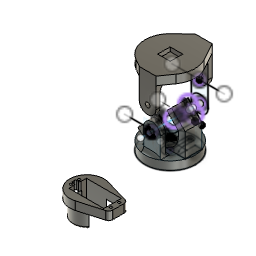
2 Axis Animitronic Neck (Autodesk Fusion 360 design; units mm, degrees)
Autodesk Fusion 360 part; units mm, degrees
sketch "Sketch1" plane through (0, 0, 0) normal (0, 0, 1) x (1, 0, 0)
  circle A0 centre (0, 0) radius 15 construction
  line L0 (0, 5) -> (-39.2157, 5) construction
  line L1 (0, -5) -> (-39.2157, -5) construction
  circle A1 centre (-14.1421, -5) radius 1.5
  circle A2 centre (-14.1421, 5) radius 1.5
  line L2 (-14.1421, -5) -> (-14.1421, 5) construction
  line L3 (33.8579, -5) -> (33.8579, 5) construction
  circle A3 centre (33.8579, 5) radius 1.5
  circle A4 centre (33.8579, -5) radius 1.5
  line L4 (0, -10.5) -> (30.8579, -10.5)
  line L5 (0, 10.5) -> (30.8579, 10.5)
  line L6 (-14.1421, 0) -> (33.8579, 0) construction
  line L7 (30.8579, 0) -> (30.8579, -10.5)
  line L8 (30.8579, 0) -> (30.8579, 10.5)
  line L9 (-11.1421, 0) -> (-11.1421, 10.5)
  line L10 (-11.1421, 0) -> (-11.1421, -10.5)
  line L11 (37.8579, 0) -> (37.8579, 10.5)
  line L12 (37.8579, 0) -> (37.8579, -10.5)
  line L13 (37.8579, 10.5) -> (5.6339, 19.7106)
  line L14 (37.8579, -10.5) -> (5.6339, -19.7106)
  line L15 (0, 10.5) -> (-11.1421, 10.5)
  line L16 (0, -10.5) -> (-11.1421, -10.5)
  arc A5 (5.6339, 19.7106) -> (5.6339, -19.7106) centre (0, 0) ccw
  arc A6 (12.8896, 10.5) -> (12.8896, -10.5) centre (0, 0) ccw
  dimension "d1" = 33.25
  dimension "d3" = 30
  dimension "d6" = 3
  dimension "d7" = 3
  dimension "d8" = 48
  dimension "d9" = 3
  dimension "d10" = 3
  constraint coincident A0.centre A5.centre
  constraint coincident A0 A1.centre
  constraint coincident L1 A1.centre
  constraint coincident A0 A2.centre
  constraint coincident L0 A2.centre
  constraint coincident A1.centre L2.start
  constraint coincident A2.centre L2.end
  constraint coincident L3.end A3.centre
  constraint coincident L3.start A4.centre
  constraint midpoint L2 L6.start
  constraint midpoint L3 L6.end
  constraint perpendicular L3 L6
  constraint coincident L5 A6.start
  constraint coincident L4 A6.end
  measures "d1" diameter of A6
  measures "d3" diameter of A0
  measures "d6" diameter of A1
  measures "d7" diameter of A2
  measures "d9" diameter of A3
  measures "d10" diameter of A4
extrude "Extrude1" add sketch "Sketch1" along normal blind 10 contours L4 L5 L9 L10 L15 L16 A6 | L11 L12 L13 L14 A5 makes body 1
extrude "Extrude2" add sketch "Sketch1" against normal blind 20 contours L4 L5 L9 L10 L15 L16 A6 bodies 1
sketch "Sketch2" plane through (0, 0, -20) normal (0, 0, -1) x (1, 0, 0)
  circle A0 centre (-14.1421, 5) radius 1.5
  circle A1 centre (-14.1421, -5) radius 1.5
  line L0 (12.8896, -10.5) -> (-11.1421, -10.5)
  line L1 (-11.1421, -10.5) -> (-11.1421, 10.5)
  line L2 (-11.1421, 10.5) -> (12.8896, 10.5)
  arc A2 (12.8896, 10.5) -> (12.8896, -10.5) centre (0, 0) ccw
  line L3 (-11.1421, 0) -> (-19.0195, 0)
  line L4 (-19.0195, 0) -> (-19.0195, -5)
  line L5 (-19.0195, -5) -> (-11.1421, -5)
  line L6 (-19.0195, 0) -> (-19.0195, 5)
  line L7 (-19.0195, 5) -> (-11.1421, 5)
  dimension "d20" = 5
  dimension "d21" = 5
  constraint midpoint L1 L3.start
  constraint perpendicular L1 L3
  constraint perpendicular L3 L4
  constraint coincident L1 L5.end
  constraint perpendicular L1 L5
  constraint perpendicular L3 L6
  constraint coincident L1 L7.end
  constraint perpendicular L1 L7
  measures "d20" distance of L3.end L4.end
  measures "d21" distance of L3.end L6.end
extrude "Extrude3" add sketch "Sketch1" against normal blind 20 contours A1 | A2 bodies 1
extrude "Extrude4" cut sketch "Sketch2" against normal blind 20 contours A0 L1 A2 L3 L7 | A0 L7 | A1 L1 A2 L3 L5 | A1 L5 picked at (-14.0309, 4.5125) picked at (-13.8921, -4.567) bodies 1
sketch "Sketch3" plane through (0, 0, 10) normal (0, 0, 1) x (-1, 0, 0)
  circle A0 centre (14.1421, -5) radius 1.5
  line L0 (-30.8579, -10.5) -> (-30.8579, 10.5)
  line L1 (-30.8579, 10.5) -> (11.1421, 10.5)
  line L2 (11.1421, 10.5) -> (11.1421, -10.5)
  line L3 (11.1421, -10.5) -> (-30.8579, -10.5)
  circle A1 centre (14.1421, 5) radius 1.5
  circle A2 centre (-33.8579, -5) radius 1.5
  circle A3 centre (-33.8579, 5) radius 1.5
  line L4 (-37.8579, 10.5) -> (-37.8579, -10.5)
  line L5 (-37.8579, -10.5) -> (-5.6339, -19.7106)
  arc A4 (-5.6339, -19.7106) -> (-5.6339, 19.7106) centre (0, 0) ccw
  line L6 (-5.6339, 19.7106) -> (-37.8579, 10.5)
  line L7 (11.1421, 0) -> (16.1421, 0)
  line L8 (16.1421, 0) -> (16.1421, -2.5)
  line L9 (16.1421, -2.5) -> (11.1421, -2.5)
  line L10 (16.1421, 0) -> (16.1421, 2.5)
  line L11 (16.1421, 2.5) -> (11.1421, 2.5)
  dimension "d26" = 5
  dimension "d27" = 2.5
  dimension "d28" = 2.5
  constraint midpoint L2 L7.start
  constraint perpendicular L2 L7
  constraint perpendicular L7 L8
  constraint coincident L2 L9.end
  constraint perpendicular L2 L9
  constraint perpendicular L7 L10
  constraint coincident L2 L11.end
  constraint perpendicular L2 L11
  measures "d26" distance of L7.start L7.end
  measures "d27" distance of L7.end L8.end
  measures "d28" distance of L7.end L10.end
extrude "Extrude5" cut sketch "Sketch3" against normal blind 21 contours L2 L7 L8 L9 | L2 L7 L10 L11 bodies 1
fillet "Fillet1" radius 1.5 2 edges at (-16.1421, 2.5, 5) (-11.1421, 2.5, 5) on bodies 1
fillet "Fillet2" radius 1.5 2 edges at (-16.1421, -2.5, 5) (-11.1421, -2.5, 5) on bodies 1
fillet "Fillet3" radius 5 2 edges at (37.8579, -10.5, 5) (37.8579, 10.5, 5) on bodies 1
fillet "Fillet4" radius 2 2 edges at (-3.1243, 16.3288, -20) (-3.1243, -16.3288, -20) on bodies 1
move_body "Move1" bodies 1 to x (1, 0, 0) y (0, 1, 0) z (0, 0, 1) at (0, -100, 0)
sketch "Sketch1 (2)" plane through (0, 0, 0) normal (0, 0, 1) x (1, 0, 0) in component "mid mount"
  circle A0 centre (0, 0) radius 30
  line L0 (0, 0) -> (0, 24)
  line L1 (4, 12.2838) -> (4, 24)
  line L2 (-4, 12.2838) -> (-4, 24)
  arc A1 (4, 24) -> (-4, 24) centre (0, 24) ccw
  arc A2 (-6.4033, 4.1398) -> (6.4033, 4.1398) centre (0, 0) ccw
  circle A3 centre (0, 24) radius 1.5
  arc A4 (-6.4033, 4.1398) -> (-4, 12.2838) centre (-19, 12.2838) ccw
  arc A5 (4, 12.2838) -> (6.4033, 4.1398) centre (19, 12.2838) ccw
  dimension "d39" = 60
  dimension "d40" = 15.25
  dimension "d41" = 24
  dimension "d42" = 8
  dimension "d45" = 3
  dimension "d46" = 15
  dimension "d47" = 15
  constraint coincident A0.centre L0.start
  constraint concentric A0 A2
  constraint vertical L0
  constraint coincident L0.end A1.centre
  constraint concentric A1 A3
  constraint tangent L2 A4
  constraint tangent A2 A4
  constraint tangent L1 A5
  constraint tangent A2 A5
  measures "d39" diameter of A0
  measures "d40" diameter of A2
  measures "d41" distance of A0.centre L0.end
  measures "d42" diameter of A1
  measures "d45" diameter of A3
  measures "d46" radius of A4
  measures "d47" radius of A5
extrude "Extrude1'" add sketch "Sketch1 (2)" along normal blind 10 separate body contours A0 | L1 L2 A1 A2 A4 A5 | A3 makes body 2 in component "mid mount"
extrude "Extrude2'" cut sketch "Sketch1 (2)" along normal blind 7 contours L1 L2 A1 A2 A4 A5 bodies 2 in component "mid mount"
sketch "Sketch2 (2)" plane through (0, 0, 10) normal (0, 0, 1) x (-1, 0, 0) in component "mid mount"
  circle A0 centre (0, 0) radius 30
  line L0 (0, 0) -> (54.6614, 0)
  line L1 (0, 0) -> (-20, 0)
  line L2 (-20, 0) -> (-20, 10)
  line L3 (-20, 10) -> (-28, 10)
  line L4 (-28, 10) -> (-28, -10)
  line L5 (-28, -10) -> (-20, -10)
  line L6 (-20, -10) -> (-20, 0)
  dimension "d52" = 20
  dimension "d53" = 10
  dimension "d54" = 8
  dimension "d55" = 20
  constraint coincident A0.centre L0.start
  constraint horizontal L0
  constraint parallel L0 L1
  constraint perpendicular L0 L2
  constraint perpendicular L2 L3
  constraint perpendicular L0 L4
  constraint perpendicular L4 L5
  constraint perpendicular L1 L6
  measures "d52" distance of A0.centre L1.end
  measures "d53" distance of L1.end L2.end
  measures "d54" distance of L2.end L3.end
  measures "d55" distance of L3.end L4.end
extrude "Extrude3'" add sketch "Sketch2 (2)" along normal blind 25 contours L2 L3 L4 L5 L6 bodies 2 in component "mid mount"
sketch "Sketch3 (2)" plane through (0, 10, 0) normal (0, 1, 0) x (-1, 0, 0) in component "mid mount"
  line L0 (-28, 10) -> (-20, 10)
  line L1 (-20, 10) -> (-20, 35)
  line L2 (-20, 35) -> (-28, 35)
  line L3 (-28, 35) -> (-28, 10)
  line L4 (-20, 35) -> (-5.8579, 49.1421)
  line L5 (-20, 35) -> (25, 35) construction
  line L6 (-28, 38.3137) -> (-11.5147, 54.799)
  line L7 (-28, 35) -> (-28, 38.3137)
  line L8 (-20, 35) -> (-25.6569, 40.6569)
  line L9 (-5.8579, 49.1421) -> (-11.5147, 54.799)
  dimension "d59" = 45
  dimension "d61" = 20
  constraint horizontal L5
  constraint coincident L1.end L2.start
  constraint coincident L2.end L3.start
  constraint perpendicular L2 L7
  constraint perpendicular L6 L8
  constraint coincident L6 L8.end
  measures "d59" angle of L4 L5
extrude "Extrude4'" add sketch "Sketch3 (2)" against normal blind 20 contours L2 L6 L7 L8 | L4 L6 L8 L9 bodies 2 in component "mid mount"
sketch "Sketch4" plane through (0, 10, 0) normal (0, 1, 0) x (-1, 0, 0) in component "mid mount"
  line L0 (-28, 10) -> (-20, 10)
  line L1 (-20, 10) -> (-20, 35)
  line L2 (-20, 35) -> (-5.8579, 49.1421)
  line L3 (-5.8579, 49.1421) -> (-11.5147, 54.799)
  line L4 (-11.5147, 54.799) -> (-28, 38.3137)
  line L5 (-28, 38.3137) -> (-28, 10)
  line L6 (-8.6863, 51.9706) -> (-11.5147, 49.1421)
  line L7 (-11.5147, 49.1421) -> (-18.5858, 42.0711)
  circle A0 centre (-11.5147, 49.1421) radius 1.5
  circle A1 centre (-18.5858, 42.0711) radius 1.5
  line L8 (-11.5147, 49.1421) -> (23.1335, 14.4939)
  line L9 (-18.5858, 42.0711) -> (16.0624, 7.4228)
  circle A2 centre (23.1335, 14.4939) radius 1.5
  circle A3 centre (16.0624, 7.4228) radius 1.5
  line L10 (-20, 35) -> (21.4524, -6.4524)
  line L11 (-20, 35) -> (-5.8579, 49.1421)
  line L12 (8.9914, 6.0086) -> (23.1335, 20.1508)
  line L13 (8.9914, 6.0086) -> (14.6482, 0.3518)
  line L14 (14.6482, 0.3518) -> (28.1635, 13.867)
  line L15 (23.1335, 14.4939) -> (25.9619, 11.6655)
  dimension "d64" = 4
  dimension "d65" = 10
  dimension "d66" = 3
  dimension "d67" = 3
  dimension "d68" = 49
  dimension "d69" = 49
  dimension "d70" = 3
  dimension "d71" = 3
  dimension "d72" = 41
  dimension "d75" = 8
  constraint midpoint L3 L6.start
  constraint perpendicular L3 L6
  constraint perpendicular L3 L7
  constraint coincident L6.end L7.start
  constraint coincident L7.end A1.centre
  constraint perpendicular L2 L8
  constraint perpendicular L7 L9
  constraint coincident L8.end A2.centre
  constraint coincident L9.end A3.centre
  constraint coincident L1.end L2.start
  constraint perpendicular L2 L10
  constraint coincident L2.end L3.start
  constraint coincident L10 L13.end
  constraint perpendicular L12 L13
  constraint perpendicular L10 L14
  constraint coincident L14 L15.end
  constraint perpendicular L14 L15
  measures "d64" distance of L6.start L6.end
  measures "d65" distance of L6.end L7.end
  measures "d66" diameter of A0
  measures "d67" diameter of A1
  measures "d68" distance of L6.end L8.end
  measures "d69" distance of L7.end L9.end
  measures "d70" diameter of A2
  measures "d71" diameter of A3
  measures "d75" distance of L12.start L13.end
extrude "Extrude5'" cut sketch "Sketch4" against normal blind 30 contours L2 L9 L10 L11 L12 | L2 L8 L9 L11 L12 bodies 2 in component "mid mount"
extrude "Extrude6" cut sketch "Sketch4" along normal blind 28 contours L2 L9 L10 L11 L12 | L8 A2 L10 L12 L13 L14 L15 | L8 A2 L15 | A3 picked at (23.2452, 13.503) bodies 2 in component "mid mount"
sketch "Sketch5" plane through (-7.5, 0, 7.5) normal (-0.707107, 0, 0.707107) x (0, -1, 0) in component "mid mount"
  line L0 (20, 3.5355) -> (-29.5804, 3.5355)
  ellipse E0 centre (0, 10.6066) end of major axis (0, 53.033) minor radius 30 (-29.5804, 3.5355) -> (-26.1807, -10.1091) ccw
  line L1 (-26.1807, -10.1091) -> (-10, -10.1091)
  line L2 (-10, -10.1091) -> (-10, -2.1091)
  line L3 (-10, -2.1091) -> (20, -2.1091)
  line L4 (20, -2.1091) -> (20, 3.5355)
  line L5 (-10, -2.1091) -> (-10, -10.1091)
  line L6 (-10, -2.1091) -> (10, -2.1091)
  line L7 (-10, -10.1091) -> (10, -10.1091)
  line L8 (10, -2.1091) -> (10, -10.1091)
  dimension "d78" = 20
  dimension "d79" = 20
  constraint coincident L2.end L3.start
  constraint coincident L1.end L2.start
  constraint perpendicular L2 L6
  constraint perpendicular L2 L7
  measures "d78" distance of L2.end L6.end
  measures "d79" distance of L1.end L7.end
extrude "Extrude7" add sketch "Sketch5" along normal blind 20 contours L2 L3 L5 L6 L7 L8 bodies 2 in component "mid mount"
extrude "Extrude8" cut sketch "Sketch4" against normal blind 15 contours L7 A1 L9 | L7 A1 L9 | L6 A0 L8 | L6 L7 A0 | L7 A0 L8 | L8 A2 L15 | L8 A2 L15 | A3 bodies 2 in component "mid mount"
extrude "Extrude9" cut sketch "Sketch1 (2)" along normal blind 10 contours A3 bodies 2 in component "mid mount"
sketch "Sketch6" plane through (0, 10, 0) normal (0, 1, 0) x (-1, 0, 0) in component "mid mount"
  line L0 (-16.8837, 47.44) -> (-13.2168, 43.7732)
  line L1 (-11.5147, 49.1421) -> (-18.5858, 42.0711)
  line L2 (-15.0503, 45.6066) -> (-4.4437, 35)
  dimension "d86" = 15
  constraint perpendicular L0 L1
  constraint midpoint L1 L2.start
  constraint perpendicular L1 L2
  measures "d86" distance of L2.start L2.end
sketch "Sketch7" plane through (0, 0, 0) normal (0, 1, 0) x (1, 0, 0) in component "mid mount"
  point P0 (4.4437, -35)
ref_plane "WorkPlane1" through (15.0503, 10, 45.6066) normal (-0.707107, 0, 0.707107) x (0, -1, 0) in component "mid mount"
sketch "Sketch8" plane through (-15.2782, 0, 15.2782) normal (-0.707107, 0, 0.707107) x (0, -1, 0) in component "mid mount"
  line L0 (-10, 27.8909) -> (40, 27.8909)
  line L1 (-10, 27.8909) -> (-31, 27.8909)
  point P0 (-10, 27.8909)
  dimension "d88" = 50
  dimension "d89" = 21
  constraint coincident P0 L0.start
  measures "d88" distance of P0 L0.end
  measures "d89" distance of P0 L1.end
sketch "Sketch9" plane through (0, 0, 10) normal (0, 0, 1) x (-1, 0, 0) in component "mid mount"
  line L0 (5, 20) -> (-27.1003, 20)
  line L1 (-4.4437, -10) -> (-4.4437, 40)
  line L2 (-4.4437, 20) -> (-14.4437, 20)
  line L3 (-14.4437, 20) -> (-14.4437, 28.5869)
  line L4 (-4.4437, 20) -> (5.5563, 20)
  line L5 (5.5563, 20) -> (5.5563, 30.6716)
  line L6 (5.5563, 20) -> (30.4984, 20)
  circle A0 centre (0, 0) radius 30
  line L7 (-14.4437, 20) -> (-14.4437, 26.2941)
  line L8 (-14.4437, 26.2941) -> (5.5563, 26.2941)
  point P0 (5, 20)
  dimension "d90" = 10
  dimension "d91" = 10
  dimension "d92" = 60
  constraint horizontal L0
  constraint coincident P0 L0.start
  constraint coincident L0 L2.start
  constraint coincident L1 L2.start
  constraint perpendicular L1 L2
  constraint perpendicular L0 L3
  constraint perpendicular L1 L4
  constraint perpendicular L4 L5
  constraint perpendicular L5 L6
  constraint coincident A0.centre origin
  constraint coincident A0 L7.end
  constraint coincident L3 L7.end
  constraint coincident L5 L8.end
  constraint perpendicular L5 L8
  measures "d90" distance of L2.start L2.end
  measures "d91" distance of L2.start L4.end
  measures "d92" diameter of A0
extrude "Extrude10" add sketch "Sketch9" along normal blind 35 contours L0 L1 L4 L5 L8 | L0 L1 L2 L3 L7 L8 bodies 2 in component "mid mount"
sketch "Sketch10" plane through (0, -26.2941, 0) normal (0, -1, 0) x (1, 0, 0) in component "mid mount"
  line L0 (-5.5563, 10) -> (14.4437, 10)
  line L1 (14.4437, 10) -> (14.4437, 45)
  line L2 (14.4437, 45) -> (-5.5563, 45)
  line L3 (-5.5563, 45) -> (-5.5563, 10)
  circle A0 centre (4.4437, 35) radius 2.5
  point P0 (4.4437, 35)
  dimension "d95" = 5
  constraint coincident P0 A0.centre
  measures "d95" diameter of A0
extrude "Extrude11" add sketch "Sketch10" along normal blind 5 contours A0 bodies 2 in component "mid mount"
fillet "Fillet1'" radius 2 1 edges at (2.1128, -31.2941, 34.096) on bodies 2 in component "mid mount"
fillet "Fillet2'" radius 10 1 edges at (-5.5563, -23.1471, 45) on bodies 2 in component "mid mount"
fillet "Fillet3'" radius 10 1 edges at (14.4437, -23.1471, 45) on bodies 2 in component "mid mount"
ref_plane "WorkPlane1" through (0, 0, 60) normal (0, 0, 1) x (-1, 0, 0) in component "Upper mount"
sketch "Sketch1 (3)" plane through (0, 0, 60) normal (0, 0, 1) x (1, 0, 0) in component "Upper mount"
  circle A0 centre (0, 0) radius 30
  line L0 (0, 0) -> (0, -41.1075)
  line L1 (4.4437, 10) -> (4.4437, -40)
  line L2 (4.4437, 10) -> (4.4437, 31)
  line L3 (4.4437, 31) -> (-19.2926, 31)
  dimension "d105" = 60
  constraint coincident A0.centre L0.start
  constraint vertical L0
  constraint coincident L2.end L3.start
  constraint perpendicular L2 L3
  measures "d105" diameter of A0
ref_plane "WorkPlane2" through (-19.2926, 31, 60) normal (0, 1, 0) x (-1, 0, 0) in component "Upper mount"
sketch "Sketch2 (3)" plane through (0, 31, 0) normal (0, 1, 0) x (1, 0, 0) in component "Upper mount"
  circle A0 centre (4.4437, -35) radius 4
  circle A1 centre (4.4437, -35) radius 10
  line L0 (4.4437, -60) -> (33.9028, -60)
  line L1 (14.4437, -35) -> (14.4437, -60)
  line L2 (4.4437, -60) -> (-28.6272, -60)
  line L3 (-5.5563, -35) -> (-5.5563, -60)
  point P0 (4.4437, -35)
  point P1 (4.4437, -60)
  dimension "d106" = 8
  dimension "d107" = 20
  constraint coincident P0 A0.centre
  constraint horizontal L0
  constraint coincident P1 L0.start
  constraint coincident A1 L1.start
  constraint coincident L0 L1.end
  constraint perpendicular L0 L1
  constraint tangent A1 L1
  constraint parallel L0 L2
  constraint coincident A1 L3.start
  constraint coincident L2 L3.end
  constraint perpendicular L2 L3
  constraint tangent A1 L3
  measures "d106" diameter of A0
  measures "d107" diameter of A1
extrude "Extrude1''" add sketch "Sketch2 (3)" along normal blind 5 separate body contours A0 | A1 | A1 L0 L1 L2 L3 makes body 3 in component "Upper mount"
extrude "Extrude2''" add sketch "Sketch2 (3)" against normal blind 1.5 contours A0 bodies 3 in component "Upper mount"
sketch "Sketch3 (3)" plane through (0, 0, 60) normal (0, 0, 1) x (1, 0, 0) in component "Upper mount"
  line L0 (-5.5563, 36) -> (-20.5856, 21.8228)
  circle A0 centre (0, 0) radius 30
  line L1 (14.4437, 36) -> (26.2893, 14.4524)
  line L2 (-5.5563, 36) -> (14.4437, 36)
  point P0 (-5.5563, 36)
  point P1 (14.4437, 36)
  constraint coincident P0 L0.start
  constraint tangent L0 A0
  constraint coincident A0 L0.end
  constraint coincident P1 L1.start
  constraint tangent A0 L1
  constraint coincident A0 L1.end
move_body "Move1'" bodies 3 to x (1, 0, 0) y (0, 1, 0) z (0, 0, 1) at (0, -62.5, 0) in component "Upper mount"
extrude "Extrude3''" add sketch "Sketch2 (3)" along normal blind 5 separate body contours A0 | A1 | A1 L0 L1 L2 L3 makes body 4 in component "Upper mount"
extrude "Extrude4''" add sketch "Sketch2 (3)" against normal blind 1.5 contours A0 bodies 4 in component "Upper mount"
extrude "Extrude5''" cut 1 faces at (4.147, -33, 33.8176) along direction (0, 1, 0) blind 1.5 on bodies 3 bodies 3 in component "Upper mount"
sketch "Sketch4 (2)" plane through (0, -31.5, 0) normal (0, -1, 0) x (1, 0, 0) in component "Upper mount"
  arc A0 (-5.5563, 35) -> (14.4437, 35) centre (4.4437, 35) ccw
  line L0 (14.4437, 35) -> (14.4437, 60)
  line L1 (14.4437, 60) -> (-5.5563, 60)
  line L2 (-5.5563, 60) -> (-5.5563, 35)
  circle A1 centre (4.4437, 35) radius 2.875
  dimension "d118" = 5.75
  constraint concentric A0 A1
  measures "d118" diameter of A1
extrude "Extrude12" cut sketch "Sketch4 (2)" against normal blind 5 contours A1 bodies 2 in component "mid mount"
extrude "Extrude6'" cut sketch "Sketch4 (2)" against normal blind 5 contours A1 bodies 3 in component "Upper mount"
sketch "Sketch5 (2)" plane through (0, 0, 60) normal (0, 0, 1) x (1, 0, 0) in component "Upper mount"
  line L0 (-5.5563, -31.5) -> (-15.1365, -25.9015)
  circle A0 centre (0, 0) radius 30
  line L1 (14.4437, -31.5) -> (24.4747, -17.3491)
  line L2 (-5.5563, -31.5) -> (14.4437, -31.5)
  point P0 (-5.5563, -31.5)
  point P1 (14.4437, -31.5)
  constraint coincident P0 L0.start
  constraint tangent L0 A0
  constraint coincident A0 L0.end
  constraint coincident P1 L1.start
  constraint tangent A0 L1
  constraint coincident A0 L1.end
extrude "Extrude7'" add sketch "Sketch3 (3)" sketch "Sketch5 (2)" sketch "Sketch1 (3)" along normal blind 10 contours L0 A0 L1 L2 of sketch 2 contours L0 A0 L1 L2 of sketch 3 bodies 3 4 in component "Upper mount"
sketch "Sketch6 (2)" plane through (0, 29.5, 0) normal (0, -1, 0) x (1, 0, 0) in component "Upper mount"
  circle A0 centre (4.4437, 35) radius 4
  circle A1 centre (4.4437, 35) radius 1.75
  dimension "d125" = 3.5
  constraint concentric A0 A1
  measures "d125" diameter of A1
extrude "Extrude8'" cut sketch "Sketch6 (2)" against normal blind 23 contours A1 bodies 3 in component "Upper mount"
move_body "Move2" bodies 3 to x (1, 0, 0) y (0, 1, 0) z (0, 0, 1) at (0, 0, 30) in component "Upper mount"
extrude "Extrude13" add 1 faces at (4.2582, -26.5, 33.2487) along direction (0, -1, 0) blind 5 on bodies 2 bodies 2 in component "mid mount"
fillet "Fillet4'" radius 2 1 edges at (2.1128, -31.5, 34.096) on bodies 2 in component "mid mount"
fillet "Fillet1''" radius 10 1 edges at (4.4437, -26.5, 90) on bodies 3 in component "Upper mount"
fillet "Fillet2''" radius 10 1 edges at (4.4437, 31, 90) on bodies 3 in component "Upper mount"
fillet "Fillet5" radius 20 1 edges at (20, 0, 10) on bodies 2 in component "mid mount"
fillet "Fillet6" radius 5 1 edges at (4.7218, -20, 10) on bodies 2 in component "mid mount"
fillet "Fillet7" radius 5 1 edges at (4.4437, -26.2941, 10) on bodies 2 in component "mid mount"
sketch "Sketch7 (2)" plane through (0, 0, 100) normal (0, 0, 1) x (-1, 0, 0) in component "Upper mount"
  line L0 (5.5563, -36) -> (20.5856, -21.8228)
  arc A0 (20.5856, -21.8228) -> (15.1365, 25.9015) centre (0, 0) ccw
  line L1 (15.1365, 25.9015) -> (5.5563, 31.5)
  line L2 (5.5563, 31.5) -> (-14.4437, 31.5)
  line L3 (-14.4437, 31.5) -> (-24.4747, 17.3491)
  arc A1 (-24.4747, 17.3491) -> (-26.2893, -14.4524) centre (0, 0) ccw
  line L4 (-26.2893, -14.4524) -> (-14.4437, -36)
  line L5 (-14.4437, -36) -> (5.5563, -36)
  line L6 (7.5, 7.5) -> (-7.5, 7.5)
  line L7 (-7.5, 7.5) -> (-7.5, -7.5)
  line L8 (-7.5, -7.5) -> (7.5, -7.5)
  line L9 (7.5, -7.5) -> (7.5, 7.5)
  line L10 (7.5, 7.5) -> (-7.5, -7.5) construction
  line L11 (-7.5, 7.5) -> (7.5, -7.5) construction
  dimension "d142" = 15
  dimension "d143" = 15
  constraint horizontal L6
  constraint perpendicular L6 L7
  constraint parallel L6 L8
  constraint parallel L7 L9
  constraint coincident L10 A0.centre
  constraint coincident L11 A0.centre
  constraint coincident A0.centre A1.centre
  measures "d142" distance of L7.end L8.end
  measures "d143" distance of L6.end L7.end
extrude "Extrude9'" cut sketch "Sketch7 (2)" against normal blind 5 contours L6 L7 L8 L9 bodies 3 in component "Upper mount"
fillet "Fillet3''" radius 1 1 edges at (1.7632, -26.5, 63.9604) on bodies 3 in component "Upper mount"
sketch "Sketch8 (2)" plane through (0, 31, 0) normal (0, -1, 0) x (1, 0, 0) in component "Upper mount"
  line L0 (14.4437, 80) -> (-5.5563, 80)
  line L1 (-5.5563, 80) -> (-5.5563, 65)
  arc A0 (-5.5563, 65) -> (14.4437, 65) centre (4.4437, 65) ccw
  line L2 (14.4437, 65) -> (14.4437, 80)
  circle A1 centre (4.4437, 65) radius 4
  line L3 (4.4437, 65) -> (4.4437, 95)
  line L4 (8.2437, 65) -> (8.2437, 95)
  line L5 (0.6437, 65) -> (0.6437, 95)
  line L6 (0.6437, 95) -> (8.2437, 95)
  line L7 (0.6437, 73.7659) -> (8.2437, 73.7659)
  dimension "d148" = 30
  dimension "d149" = 3.8
  dimension "d150" = -3.8
  constraint perpendicular L0 L3
  constraint coincident A0.centre A1.centre
  constraint perpendicular L4 L6
  constraint coincident L5 L7.start
  constraint coincident L4 L7.end
  constraint perpendicular L4 L7
  measures "d148" distance of A0.centre L3.end
extrude "Extrude10'" cut sketch "Sketch8 (2)" along normal blind 10 contours L0 L3 L4 L7 | L0 L3 L4 L6 | L0 L3 L5 L7 | L0 L3 L5 L6 bodies 3 in component "Upper mount"
fillet "Fillet4''" radius 2 1 edges at (4.4437, 21, 90) on bodies 3 in component "Upper mount"
fillet "Fillet5'" radius 2 1 edges at (8.2437, 26, 95) on bodies 3 in component "Upper mount"
fillet "Fillet6'" radius 2 1 edges at (0.6437, 26, 95) on bodies 3 in component "Upper mount"
component "mid mount" placed x (1, 0, 0) y (0, 1, 0) z (0, 0, 1) at (0, 0, 0)
component "Upper mount" placed x (1, 0, 0) y (0, 1, 0) z (0, 0, 1) at (0, 0, 0)
